6mm Pushbutton Cover (Autodesk Fusion 360 design; units mm, degrees)
part number: 2026-09-01-20-00-21-543
Autodesk Fusion 360 part; units mm, degrees
sketch "Sketch1" plane through (0, 0, 0) normal (0, 0, 1) x (1, 0, 0)
  circle A0 centre (0, 0) radius 3
  circle A1 centre (0, 0) radius 4
  line L0 (2.8368, 2.8201) -> (3.1526, -2.462)
  line L1 (-2.9947, -0.179) -> (2.9947, 0.179) construction
  line L2 (-0.179, 2.9947) -> (0.179, -2.9947) construction
  line L3 (-3.1526, 2.462) -> (-2.8368, -2.8201)
  dimension "d1" = 6
  dimension "d2" = 8
  constraint coincident A0.centre A1.centre
  constraint coincident A1 L0.start
  constraint coincident A1 L0.end
  constraint tangent A0 L0
  constraint coincident A0 L1.start
  constraint coincident A0 L1.end
  constraint perpendicular A0 L1
  constraint coincident A0 L2.start
  constraint coincident A0 L2.end
  constraint perpendicular A0 L2
  constraint perpendicular L1 L2
  constraint perpendicular L0 L1
  constraint symmetric L0.start L2 L3.start
  constraint symmetric L0.end L2 L3.end
  measures "d1" diameter of A0
  measures "d2" diameter of A1
extrude "Extrude1" add sketch "Sketch1" along normal blind 1.3 contours A0 A1 L0 L3 | A0 A1 L0 L3 makes body 1
extrude "Extrude2" add sketch "Sketch1" along normal blind 7 separate body contours A0 makes body 2
